Autodesk Fusion 360 part; units mm, degrees
(part 2 of 2)
  spline S213 degree 3 poles (-42.3057, 26.3614) (-42.1542, 25.8877) (-42.1542, 25.2814) (-42.3152, 24.8267) knots 0 0 0 0 1 1 1 1
  line L138 (-47.5871, 5.9227) -> (-49.226, 5.9227)
  line L139 (-49.226, 5.9227) -> (-49.2118, 5.648)
  spline S214 degree 3 poles (-49.2118, 5.648) (-49.1976, 5.3828) (-49.1976, 5.378) (-49.0365, 5.3544) knots 0 0 0 0 1 1 1 1
  line L140 (-49.0365, 5.3544) -> (-48.8802, 5.3307)
  line L141 (-48.8802, 5.3307) -> (-48.9844, 5.2359)
  spline S215 degree 3 poles (-48.9844, 5.2359) (-49.3586, 4.9044) (-49.2733, 4.1986) (-48.8281, 3.8907) knots 0 0 0 0 1 1 1 1
  spline S216 degree 3 poles (-48.8281, 3.8907) (-48.5344, 3.6918) (-48.3071, 3.635) (-47.9234, 3.6586) knots 0 0 0 0 1 1 1 1
  spline S217 degree 3 poles (-47.9234, 3.6586) (-47.4118, 3.6918) (-47.085, 3.8955) (-46.924, 4.2744) knots 0 0 0 0 1 1 1 1
  spline S218 degree 3 poles (-46.924, 4.2744) (-46.7913, 4.6012) (-46.8482, 4.9328) (-47.0803, 5.1744) knots 0 0 0 0 1 1 1 1
  line L142 (-47.0803, 5.1744) -> (-47.2034, 5.307)
  line L143 (-47.2034, 5.307) -> (-46.5782, 5.307)
  line L144 (-46.5782, 5.307) -> (-45.953, 5.307)
  line L145 (-45.953, 5.307) -> (-45.953, 5.6149)
  line L146 (-45.953, 5.6149) -> (-45.953, 5.9227)
  line L147 (-45.953, 5.9227) -> (-47.5871, 5.9227)
  spline S219 degree 3 poles (-47.4876, 4.4875) (-47.7245, 4.2318) (-48.2787, 4.2128) (-48.5202, 4.4591) knots 0 0 0 0 1 1 1 1
  spline S220 degree 3 poles (-48.5202, 4.4591) (-48.7097, 4.6439) (-48.7097, 4.9517) (-48.5202, 5.1317) knots 0 0 0 0 1 1 1 1
  spline S221 degree 3 poles (-48.5202, 5.1317) (-48.2692, 5.3686) (-47.6724, 5.3449) (-47.4734, 5.0844) knots 0 0 0 0 1 1 1 1
  spline S222 degree 3 poles (-47.4734, 5.0844) (-47.3361, 4.9138) (-47.3408, 4.6439) (-47.4876, 4.4875) knots 0 0 0 0 1 1 1 1
  spline S223 degree 3 poles (-46.1282, 21.8568) (-46.2372, 21.89) (-49.027, 21.89) (-49.136, 21.8568) knots 0 0 0 0 1 1 1 1
  spline S224 degree 3 poles (-49.136, 21.8568) (-49.207, 21.8379) (-49.2212, 21.7763) (-49.2212, 21.5252) knots 0 0 0 0 1 1 1 1
  line L148 (-49.2212, 21.5252) -> (-49.2212, 21.2221)
  line L149 (-49.2212, 21.2221) -> (-48.5107, 21.2221)
  line L150 (-48.5107, 21.2221) -> (-47.7955, 21.2221)
  line L151 (-47.7955, 21.2221) -> (-47.8097, 20.4974)
  line L152 (-47.8097, 20.4974) -> (-47.8239, 19.7774)
  line L153 (-47.8239, 19.7774) -> (-48.525, 19.7632)
  line L154 (-48.525, 19.7632) -> (-49.226, 19.749)
  line L155 (-49.226, 19.749) -> (-49.2118, 19.4317)
  line L156 (-49.2118, 19.4317) -> (-49.1976, 19.1143)
  line L157 (-49.1976, 19.1143) -> (-47.6203, 19.1001)
  line L158 (-47.6203, 19.1001) -> (-46.0477, 19.0906)
  line L159 (-46.0477, 19.0906) -> (-46.0477, 19.4222)
  line L160 (-46.0477, 19.4222) -> (-46.0477, 19.749)
  line L161 (-46.0477, 19.749) -> (-46.6256, 19.7632)
  line L162 (-46.6256, 19.7632) -> (-47.2082, 19.7774)
  line L163 (-47.2082, 19.7774) -> (-47.2082, 20.4879)
  line L164 (-47.2082, 20.4879) -> (-47.2082, 21.1984)
  line L165 (-47.2082, 21.1984) -> (-46.6256, 21.2126)
  line L166 (-46.6256, 21.2126) -> (-46.0477, 21.2268)
  line L167 (-46.0477, 21.2268) -> (-46.0477, 21.53)
  spline S225 degree 3 poles (-46.0477, 21.53) (-46.0477, 21.7763) (-46.0619, 21.8379) (-46.1282, 21.8568) knots 0 0 0 0 1 1 1 1
  line L168 (-47.6345, 10.4699) -> (-49.2212, 10.4699)
  line L169 (-49.2212, 10.4699) -> (-49.2212, 9.5463)
  line L170 (-49.2212, 9.5463) -> (-49.2212, 8.6226)
  line L171 (-49.2212, 8.6226) -> (-48.9134, 8.6226)
  line L172 (-48.9134, 8.6226) -> (-48.6055, 8.6226)
  line L173 (-48.6055, 8.6226) -> (-48.6055, 9.2384)
  line L174 (-48.6055, 9.2384) -> (-48.6055, 9.8542)
  line L175 (-48.6055, 9.8542) -> (-47.3266, 9.8542)
  line L176 (-47.3266, 9.8542) -> (-46.0477, 9.8542)
  line L177 (-46.0477, 9.8542) -> (-46.0477, 10.162)
  line L178 (-46.0477, 10.162) -> (-46.0477, 10.4699)
  line L179 (-46.0477, 10.4699) -> (-47.6345, 10.4699)
  spline S226 degree 3 poles (-46.3603, 11.9714) (-46.3793, 12.0093) (-46.4835, 12.033) (-46.6398, 12.033) knots 0 0 0 0 1 1 1 1
  spline S227 degree 3 poles (-46.6398, 12.033) (-46.8908, 12.033) (-46.8956, 12.033) (-46.9098, 12.1846) knots 0 0 0 0 1 1 1 1
  spline S228 degree 3 poles (-46.9098, 12.1846) (-46.9192, 12.2698) (-46.9382, 12.3362) (-46.9571, 12.3267) knots 0 0 0 0 1 1 1 1
  spline S229 degree 3 poles (-46.9571, 12.3267) (-46.9808, 12.322) (-47.0803, 12.3172) (-47.1845, 12.3172) knots 0 0 0 0 1 1 1 1
  spline S230 degree 3 poles (-47.1845, 12.3172) (-47.3597, 12.3172) (-47.374, 12.3077) (-47.374, 12.1799) knots 0 0 0 0 1 1 1 1
  line L180 (-47.374, 12.1799) -> (-47.374, 12.0425)
  line L181 (-47.374, 12.0425) -> (-48.0466, 12.0235)
  spline S231 degree 3 poles (-48.0466, 12.0235) (-48.8044, 12.0046) (-48.937, 11.9667) (-49.1123, 11.7062) knots 0 0 0 0 1 1 1 1
  spline S232 degree 3 poles (-49.1123, 11.7062) (-49.1928, 11.5878) (-49.2212, 11.4788) (-49.2212, 11.2799) knots 0 0 0 0 1 1 1 1
  spline S233 degree 3 poles (-49.2212, 11.2799) (-49.2212, 10.8299) (-49.2023, 10.8015) (-48.9086, 10.8015) knots 0 0 0 0 1 1 1 1
  line L182 (-48.9086, 10.8015) -> (-48.6528, 10.8015)
  line L183 (-48.6528, 10.8015) -> (-48.6528, 11.0288)
  spline S234 degree 3 poles (-48.6528, 11.0288) (-48.6528, 11.152) (-48.6292, 11.2799) (-48.596, 11.313) knots 0 0 0 0 1 1 1 1
  spline S235 degree 3 poles (-48.596, 11.313) (-48.5581, 11.3509) (-48.345, 11.3699) (-47.9566, 11.3699) knots 0 0 0 0 1 1 1 1
  line L184 (-47.9566, 11.3699) -> (-47.374, 11.3699)
  line L185 (-47.374, 11.3699) -> (-47.374, 11.081)
  line L186 (-47.374, 11.081) -> (-47.374, 10.7968)
  line L187 (-47.374, 10.7968) -> (-47.1466, 10.811)
  line L188 (-47.1466, 10.811) -> (-46.924, 10.8252)
  line L189 (-46.924, 10.8252) -> (-46.9098, 11.0952)
  line L190 (-46.9098, 11.0952) -> (-46.8956, 11.3651)
  line L191 (-46.8956, 11.3651) -> (-46.6256, 11.3794)
  line L192 (-46.6256, 11.3794) -> (-46.3556, 11.3936)
  line L193 (-46.3556, 11.3936) -> (-46.3461, 11.6541)
  spline S236 degree 3 poles (-46.3461, 11.6541) (-46.3414, 11.7962) (-46.3508, 11.943) (-46.3603, 11.9714) knots 0 0 0 0 1 1 1 1
  spline S237 degree 3 poles (-46.9145, 18.0864) (-47.0755, 18.527) (-47.5113, 18.8064) (-48.0371, 18.8064) knots 0 0 0 0 1 1 1 1
  spline S238 degree 3 poles (-48.0371, 18.8064) (-48.7665, 18.8017) (-49.2212, 18.3422) (-49.2212, 17.608) knots 0 0 0 0 1 1 1 1
  spline S239 degree 3 poles (-49.2212, 17.608) (-49.2212, 17.4328) (-49.1928, 17.2196) (-49.1597, 17.1344) knots 0 0 0 0 1 1 1 1
  spline S240 degree 3 poles (-49.1597, 17.1344) (-49.0791, 16.9497) (-48.8518, 16.6749) (-48.7807, 16.6749) knots 0 0 0 0 1 1 1 1
  spline S241 degree 3 poles (-48.7807, 16.6749) (-48.7476, 16.6749) (-48.6765, 16.7507) (-48.615, 16.8454) knots 0 0 0 0 1 1 1 1
  line L194 (-48.615, 16.8454) -> (-48.506, 17.0112)
  line L195 (-48.506, 17.0112) -> (-48.6007, 17.2149)
  spline S242 degree 3 poles (-48.6007, 17.2149) (-48.7713, 17.5654) (-48.705, 17.9396) (-48.4444, 18.1149) knots 0 0 0 0 1 1 1 1
  spline S243 degree 3 poles (-48.4444, 18.1149) (-48.1887, 18.2806) (-48.1792, 18.2617) (-48.1792, 17.4091) knots 0 0 0 0 1 1 1 1
  line L196 (-48.1792, 17.4091) -> (-48.1792, 16.6276)
  line L197 (-48.1792, 16.6276) -> (-47.895, 16.6276)
  spline S244 degree 3 poles (-47.895, 16.6276) (-47.2745, 16.6276) (-46.8529, 17.0539) (-46.8577, 17.6696) knots 0 0 0 0 1 1 1 1
  spline S245 degree 3 poles (-46.8577, 17.6696) (-46.8577, 17.8117) (-46.8861, 18.0012) (-46.9145, 18.0864) knots 0 0 0 0 1 1 1 1
  spline S246 degree 3 poles (-47.374, 17.4281) (-47.4355, 17.3238) (-47.6913, 17.1817) (-47.7529, 17.2196) knots 0 0 0 0 1 1 1 1
  spline S247 degree 3 poles (-47.7529, 17.2196) (-47.8192, 17.2623) (-47.8145, 18.1907) (-47.7481, 18.1907) knots 0 0 0 0 1 1 1 1
  spline S248 degree 3 poles (-47.7481, 18.1907) (-47.6629, 18.1907) (-47.4971, 18.0912) (-47.4118, 17.9822) knots 0 0 0 0 1 1 1 1
  spline S249 degree 3 poles (-47.4118, 17.9822) (-47.3171, 17.8733) (-47.2982, 17.5702) (-47.374, 17.4281) knots 0 0 0 0 1 1 1 1
  spline S250 degree 3 poles (-46.8956, 15.7276) (-46.9666, 15.9502) (-47.0898, 16.1539) (-47.2129, 16.2297) knots 0 0 0 0 1 1 1 1
  spline S251 degree 3 poles (-47.2129, 16.2297) (-47.3503, 16.3197) (-47.3313, 16.3292) (-47.464, 16.0734) knots 0 0 0 0 1 1 1 1
  line L198 (-47.464, 16.0734) -> (-47.5634, 15.8744)
  line L199 (-47.5634, 15.8744) -> (-47.445, 15.756)
  spline S252 degree 3 poles (-47.445, 15.756) (-47.2745, 15.5855) (-47.2745, 15.2066) (-47.445, 15.0408) knots 0 0 0 0 1 1 1 1
  spline S253 degree 3 poles (-47.445, 15.0408) (-47.5066, 14.9745) (-47.6108, 14.9224) (-47.6771, 14.9224) knots 0 0 0 0 1 1 1 1
  spline S254 degree 3 poles (-47.6771, 14.9224) (-47.7908, 14.9224) (-47.7955, 14.9271) (-47.7955, 15.3487) knots 0 0 0 0 1 1 1 1
  spline S255 degree 3 poles (-47.7955, 15.3487) (-47.7955, 15.7087) (-47.8097, 15.8081) (-47.9045, 15.9739) knots 0 0 0 0 1 1 1 1
  spline S256 degree 3 poles (-47.9045, 15.9739) (-48.1981, 16.5091) (-48.8707, 16.5328) (-49.1407, 16.0118) knots 0 0 0 0 1 1 1 1
  spline S257 degree 3 poles (-49.1407, 16.0118) (-49.2686, 15.7608) (-49.2355, 15.3155) (-49.0649, 15.0976) knots 0 0 0 0 1 1 1 1
  spline S258 degree 3 poles (-49.0649, 15.0976) (-48.9939, 15.0029) (-48.937, 14.9176) (-48.937, 14.9034) knots 0 0 0 0 1 1 1 1
  spline S259 degree 3 poles (-48.937, 14.9034) (-48.937, 14.8892) (-48.9986, 14.875) (-49.0791, 14.875) knots 0 0 0 0 1 1 1 1
  line L200 (-49.0791, 14.875) -> (-49.2212, 14.875)
  line L201 (-49.2212, 14.875) -> (-49.2212, 14.5908)
  line L202 (-49.2212, 14.5908) -> (-49.2212, 14.3066)
  line L203 (-49.2212, 14.3066) -> (-48.3781, 14.3066)
  spline S260 degree 3 poles (-48.3781, 14.3066) (-47.4829, 14.3066) (-47.2792, 14.3492) (-47.0755, 14.5813) knots 0 0 0 0 1 1 1 1
  spline S261 degree 3 poles (-47.0755, 14.5813) (-46.8861, 14.7945) (-46.7913, 15.3866) (-46.8956, 15.7276) knots 0 0 0 0 1 1 1 1
  spline S262 degree 3 poles (-48.2502, 14.9413) (-48.3781, 14.8892) (-48.5534, 14.9697) (-48.6292, 15.1118) knots 0 0 0 0 1 1 1 1
  spline S263 degree 3 poles (-48.6292, 15.1118) (-48.7239, 15.2918) (-48.7192, 15.6044) (-48.6244, 15.6992) knots 0 0 0 0 1 1 1 1
  spline S264 degree 3 poles (-48.6244, 15.6992) (-48.5202, 15.8081) (-48.3402, 15.7939) (-48.255, 15.6708) knots 0 0 0 0 1 1 1 1
  spline S265 degree 3 poles (-48.255, 15.6708) (-48.1508, 15.5239) (-48.1508, 14.9792) (-48.2502, 14.9413) knots 0 0 0 0 1 1 1 1
  spline S266 degree 3 poles (-46.8861, 12.8714) (-46.8956, 12.9282) (-46.9808, 13.0419) (-47.0708, 13.1177) knots 0 0 0 0 1 1 1 1
  spline S267 degree 3 poles (-47.0708, 13.1177) (-47.1608, 13.1982) (-47.2319, 13.274) (-47.2319, 13.2882) knots 0 0 0 0 1 1 1 1
  spline S268 degree 3 poles (-47.2319, 13.2882) (-47.2319, 13.3024) (-47.1561, 13.3119) (-47.0661, 13.3119) knots 0 0 0 0 1 1 1 1
  line L204 (-47.0661, 13.3119) -> (-46.9003, 13.3119)
  line L205 (-46.9003, 13.3119) -> (-46.9003, 13.5961)
  line L206 (-46.9003, 13.5961) -> (-46.9003, 13.8803)
  line L207 (-46.9003, 13.8803) -> (-48.0608, 13.8803)
  line L208 (-48.0608, 13.8803) -> (-49.2212, 13.8803)
  line L209 (-49.2212, 13.8803) -> (-49.2212, 13.5724)
  line L210 (-49.2212, 13.5724) -> (-49.2212, 13.2645)
  line L211 (-49.2212, 13.2645) -> (-48.6055, 13.2645)
  spline S269 degree 3 poles (-48.6055, 13.2645) (-47.7481, 13.2645) (-47.5682, 13.1793) (-47.5161, 12.7482) knots 0 0 0 0 1 1 1 1
  line L212 (-47.5161, 12.7482) -> (-47.4924, 12.5304)
  line L213 (-47.4924, 12.5304) -> (-47.1703, 12.5162)
  line L214 (-47.1703, 12.5162) -> (-46.8529, 12.5019)
  line L215 (-46.8529, 12.5019) -> (-46.8577, 12.6346)
  spline S270 degree 3 poles (-46.8577, 12.6346) (-46.8624, 12.7056) (-46.8766, 12.8146) (-46.8861, 12.8714) knots 0 0 0 0 1 1 1 1
  spline S271 degree 3 poles (-46.9192, 7.8316) (-46.9903, 8.0258) (-47.0613, 8.1348) (-47.2082, 8.2532) knots 0 0 0 0 1 1 1 1
  spline S272 degree 3 poles (-47.2082, 8.2532) (-47.3361, 8.3669) (-47.3597, 8.3621) (-47.4355, 8.2058) knots 0 0 0 0 1 1 1 1
  spline S273 degree 3 poles (-47.4355, 8.2058) (-47.5539, 7.9785) (-47.5776, 7.8648) (-47.5018, 7.8648) knots 0 0 0 0 1 1 1 1
  spline S274 degree 3 poles (-47.5018, 7.8648) (-47.4071, 7.8648) (-47.3266, 7.6564) (-47.3266, 7.3911) knots 0 0 0 0 1 1 1 1
  spline S275 degree 3 poles (-47.3266, 7.3911) (-47.3266, 7.1969) (-47.3455, 7.1448) (-47.4497, 7.0643) knots 0 0 0 0 1 1 1 1
  spline S276 degree 3 poles (-47.4497, 7.0643) (-47.5208, 7.0074) (-47.625, 6.9648) (-47.6818, 6.9648) knots 0 0 0 0 1 1 1 1
  spline S277 degree 3 poles (-47.6818, 6.9648) (-47.786, 6.9648) (-47.7908, 6.979) (-47.7908, 7.3674) knots 0 0 0 0 1 1 1 1
  spline S278 degree 3 poles (-47.7908, 7.3674) (-47.7908, 8.0116) (-48.0229, 8.3716) (-48.4681, 8.419) knots 0 0 0 0 1 1 1 1
  spline S279 degree 3 poles (-48.4681, 8.419) (-48.7381, 8.4474) (-48.9702, 8.3195) (-49.1123, 8.0732) knots 0 0 0 0 1 1 1 1
  spline S280 degree 3 poles (-49.1123, 8.0732) (-49.2876, 7.77) (-49.2355, 7.249) (-49.0176, 7.0643) knots 0 0 0 0 1 1 1 1
  spline S281 degree 3 poles (-49.0176, 7.0643) (-48.9039, 6.9743) (-48.9181, 6.9269) (-49.0649, 6.908) knots 0 0 0 0 1 1 1 1
  spline S282 degree 3 poles (-49.0649, 6.908) (-49.1928, 6.8938) (-49.1976, 6.8796) (-49.2118, 6.619) knots 0 0 0 0 1 1 1 1
  line L216 (-49.2118, 6.619) -> (-49.226, 6.349)
  line L217 (-49.226, 6.349) -> (-48.4065, 6.349)
  spline S283 degree 3 poles (-48.4065, 6.349) (-47.9566, 6.349) (-47.5066, 6.3727) (-47.4118, 6.3964) knots 0 0 0 0 1 1 1 1
  spline S284 degree 3 poles (-47.4118, 6.3964) (-47.2034, 6.458) (-46.9713, 6.709) (-46.905, 6.9506) knots 0 0 0 0 1 1 1 1
  spline S285 degree 3 poles (-46.905, 6.9506) (-46.834, 7.1969) (-46.8435, 7.6137) (-46.9192, 7.8316) knots 0 0 0 0 1 1 1 1
  spline S286 degree 3 poles (-48.2502, 6.9838) (-48.3686, 6.9364) (-48.5534, 7.0074) (-48.6339, 7.1306) knots 0 0 0 0 1 1 1 1
  spline S287 degree 3 poles (-48.6339, 7.1306) (-48.7428, 7.2964) (-48.7286, 7.6185) (-48.615, 7.7369) knots 0 0 0 0 1 1 1 1
  spline S288 degree 3 poles (-48.615, 7.7369) (-48.4965, 7.8553) (-48.2881, 7.8127) (-48.2265, 7.6611) knots 0 0 0 0 1 1 1 1
  spline S289 degree 3 poles (-48.2265, 7.6611) (-48.1555, 7.4811) (-48.1697, 7.0122) (-48.2502, 6.9838) knots 0 0 0 0 1 1 1 1
sketch "Esboço12" plane through (0, 0, 0) normal (0, 1, 0) x (-1, 0, 0)
  line L0 (-66.5, 123.25) -> (-66.5, -48.25)
  line L1 (-66.5, -48.25) -> (10.5, -48.25)
  line L2 (10.5, -48.25) -> (10.5, 123.25)
  line L3 (10.5, 123.25) -> (-66.5, 123.25)
  line L4 (0, 0) -> (-60, 0)
  line L5 (-60, 0) -> (-60, 52)
  line L6 (-60, 52) -> (0, 52)
  line L7 (0, 52) -> (0, 0)
  line L8 (0, 0) -> (8.5, 0)
  line L9 (8.5, 0) -> (8.5, -3)
  line L10 (8.5, -3) -> (-65.5, -3)
  line L11 (-65.5, -3) -> (-65.5, 55)
  line L12 (-65.5, 55) -> (8.5, 55)
  line L13 (8.5, 55) -> (8.5, -3)
  dimension "d143" = 60
  dimension "d144" = 52
  dimension "d147" = 8.5
  dimension "d148" = 3
  dimension "d149" = 58
  dimension "d150" = 74
  constraint horizontal L4
  constraint vertical L5
  constraint horizontal L6
  constraint vertical L7
  constraint coincident L4.start L7.end
  constraint perpendicular L2 L8
  constraint perpendicular L8 L9
  constraint horizontal L10
  constraint vertical L11
  constraint horizontal L12
  constraint vertical L13
  measures "d143" distance of L4.start L4.end
  measures "d144" distance of L4.start L6.end
  measures "d147" distance of L4.start L8.end
  measures "d148" distance of L8.end L9.end
  measures "d149" distance of L9.end L12.end
  measures "d150" distance of L11.end L12.end
extrude "Extrusão1''''" add sketch "Esboço12" along normal blind 5 separate body contours L9 L10 L11 L12 L13 makes body 7 in component "Component"
sketch "Esboço13" plane through (0, 0, 0) normal (0, 1, 0) x (-1, 0, 0)
  line L0 (-66.5, 123.25) -> (-66.5, -48.25)
  line L1 (-66.5, -48.25) -> (10.5, -48.25)
  line L2 (10.5, -48.25) -> (10.5, 123.25)
  line L3 (10.5, 123.25) -> (-66.5, 123.25)
  line L4 (0, 0) -> (0, 6)
  line L5 (0, 6) -> (-71, 6)
  line L6 (-71, 6) -> (-71, -49)
  line L7 (-71, -49) -> (0, -49)
  line L8 (0, -49) -> (0, 6)
  dimension "d153" = 6
  dimension "d154" = 55
  dimension "d155" = 71
  constraint coincident L4.start origin
  constraint vertical L4
  constraint horizontal L5
  constraint vertical L6
  constraint horizontal L7
  constraint vertical L8
  measures "d153" distance of L4.start L4.end
  measures "d154" distance of L4.end L7.end
  measures "d155" distance of L4.end L5.end
extrude "Extrusão1'''''" add sketch "Esboço13" along normal blind 39 separate body contours L0 L1 L4 L5 L8 makes body 8 in component "Component'"
sketch "Esboço14" plane through (-10.5, 0, 0) normal (1, 0, 0) x (0, 0, -1)
  line L0 (-123.25, 0) -> (48.25, 0)
  line L1 (48.25, 0) -> (48.25, 41)
  line L2 (48.25, 41) -> (-123.25, 41)
  line L3 (-123.25, 41) -> (-123.25, 0)
  circle A0 centre (-108.3398, 23.8891) radius 6
  dimension "d158" = 12
  measures "d158" diameter of A0
extrude "Extrusão12" cut sketch "Esboço14" against normal blind 20 contours A0 bodies 4 in component "Suporte Placa (1)"
move_face "MoverFace1" by (0, 0, 70) 1 faces at (41.1667, 45, 65.5833) on bodies 6 in component "Tampa"
sketch "Esboço15" plane through (0, 45, 0) normal (0, 1, 0) x (-1, 0, 0)
  line L0 (-67.5, 121.75) -> (-67.5, -46.75)
  arc A0 (-67.5, -46.75) -> (-65, -49.25) centre (-65, -46.75) ccw
  line L1 (-65, -49.25) -> (9, -49.25)
  arc A1 (9, -49.25) -> (11.5, -46.75) centre (9, -46.75) ccw
  line L2 (11.5, -46.75) -> (11.5, 121.75)
  arc A2 (11.5, 121.75) -> (9, 124.25) centre (9, 121.75) ccw
  line L3 (9, 124.25) -> (-65, 124.25)
  arc A3 (-65, 124.25) -> (-67.5, 121.75) centre (-65, 121.75) ccw
  line L4 (0, -49.25) -> (0, -9.25)
  line L5 (0, -9.25) -> (9, -9.25)
  line L6 (0, -9.25) -> (-6, -9.25)
  line L7 (-6, -9.25) -> (-6, 1.75)
  line L8 (-6, 1.75) -> (0, 1.75)
  line L9 (0, 1.75) -> (0, -9.25)
  line L10 (-6, -9.25) -> (-17, -9.25)
  line L11 (-17, -9.25) -> (-23, -9.25)
  line L12 (-23, -9.25) -> (-23, 1.75)
  line L13 (-23, 1.75) -> (-17, 1.75)
  line L14 (-17, 1.75) -> (-17, -9.25)
  line L15 (-23, -9.25) -> (-34, -9.25)
  line L16 (-34, -9.25) -> (-40, -9.25)
  line L17 (-40, -9.25) -> (-40, 1.75)
  line L18 (-40, 1.75) -> (-34, 1.75)
  line L19 (-34, 1.75) -> (-34, -9.25)
  line L20 (-40, -9.25) -> (-51, -9.25)
  line L21 (-51, -9.25) -> (-57, -9.25)
  line L22 (-57, -9.25) -> (-57, 1.75)
  line L23 (-57, 1.75) -> (-51, 1.75)
  line L24 (-51, 1.75) -> (-51, -9.25)
  line L25 (-57, -9.25) -> (-57, -20.25)
  line L26 (-57, -20.25) -> (-51, -20.25)
  line L27 (-51, -20.25) -> (-51, -42.25)
  line L28 (-51, -42.25) -> (-57, -42.25)
  line L29 (-57, -42.25) -> (-57, -20.25)
  line L30 (0, 0) -> (0, 49)
  line L31 (0, 49) -> (-10, 49)
  line L32 (-10, 49) -> (-10, 59)
  line L33 (-10, 59) -> (0, 59)
  line L34 (0, 59) -> (0, 49)
  dimension "d161" = 40
  dimension "d162" = 9
  dimension "d163" = 6
  dimension "d164" = 11
  dimension "d165" = 11
  dimension "d166" = 6
  dimension "d167" = 11
  dimension "d168" = 11
  dimension "d169" = 6
  dimension "d170" = 11
  dimension "d171" = 11
  dimension "d175" = 6
  dimension "d176" = 11
  dimension "d177" = 11
  dimension "d178" = 6
  dimension "d179" = 22
  dimension "d182" = 49
  dimension "d183" = 10
  dimension "d184" = 10
  constraint coincident L1 L4.start
  constraint perpendicular L1 L4
  constraint perpendicular L2 L5
  constraint horizontal L6
  constraint vertical L7
  constraint horizontal L8
  constraint vertical L9
  constraint perpendicular L0 L10
  constraint horizontal L11
  constraint vertical L12
  constraint horizontal L13
  constraint vertical L14
  constraint perpendicular L12 L15
  constraint horizontal L16
  constraint vertical L17
  constraint horizontal L18
  constraint vertical L19
  constraint perpendicular L17 L20
  constraint horizontal L21
  constraint vertical L22
  constraint horizontal L23
  constraint vertical L24
  constraint perpendicular L21 L25
  constraint horizontal L26
  constraint vertical L27
  constraint horizontal L28
  constraint vertical L29
  constraint coincident L30.start origin
  constraint perpendicular L6 L30
  constraint horizontal L31
  constraint vertical L32
  constraint horizontal L33
  constraint vertical L34
  measures "d161" distance of L4.start L4.end
  measures "d162" distance of L4.end L5.end
  measures "d163" distance of L4.end L6.end
  measures "d164" distance of L4.end L8.end
  measures "d165" distance of L6.end L10.end
  measures "d166" distance of L10.end L11.end
  measures "d167" distance of L10.end L13.end
  measures "d168" distance of L11.end L15.end
  measures "d169" distance of L15.end L16.end
  measures "d170" distance of L15.end L18.end
  measures "d171" distance of L16.end L20.end
  measures "d175" distance of L20.end L21.end
  measures "d176" distance of L20.end L23.end
  measures "d177" distance of L21.end L25.end
  measures "d178" distance of L25.end L26.end
  measures "d179" distance of L25.end L28.end
  measures "d182" distance of L30.start L30.end
  measures "d183" distance of L30.end L31.end
  measures "d184" distance of L30.end L33.end
extrude "Extrusão11'" cut sketch "Esboço15" against normal blind 10 contours L6 L7 L8 L9 L30 | L11 L12 L13 L14 | L16 L17 L18 L19 | L21 L22 L23 L24 | L26 L27 L28 L29 | L31 L32 L33 L34 bodies 6 in component "Tampa"
component "Placa 5x7" placed x (0, 0, 1) y (0, 1, 0) z (-1, 0, 0) at (65.5, 0, 65.5)
component "Tampa" placed x (1, 0, 0) y (0, 1, 0) z (0, 0, 1) at (0, 0, 0)
component "Suporte Placa (1)" placed x (1, 0, 0) y (0, 1, 0) z (0, 0, 1) at (0, 0, 0)
component "Component" placed x (1, 0, 0) y (0, 1, 0) z (0, 0, 1) at (0, 0, 9.5)
component "Component'" placed x (1, 0, 0) y (0, 1, 0) z (0, 0, 1) at (-5, 0, 0)
named bodies: "Placa 4x6"
